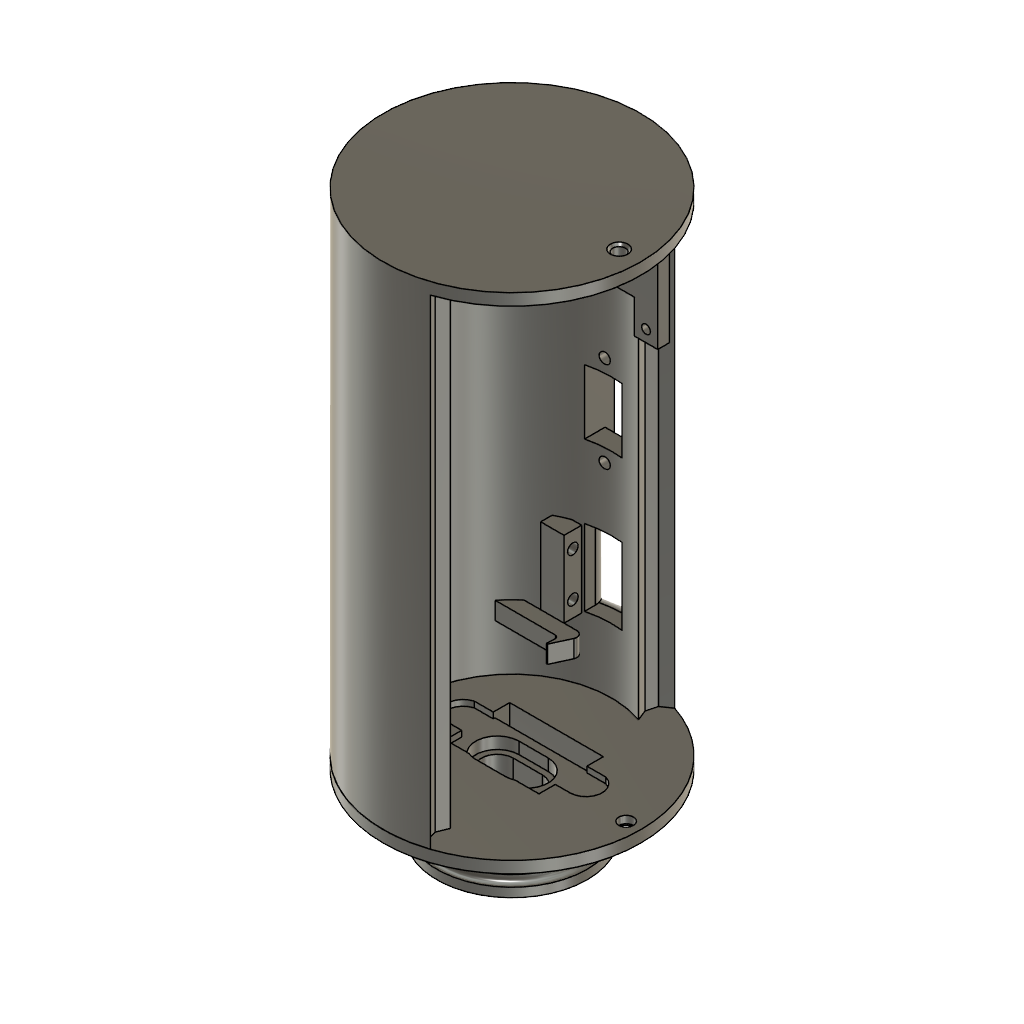
CapV3 (Autodesk Fusion 360 design; units mm, degrees)
part number: 2026-07-30-11-10-30-774
Autodesk Fusion 360 part; units mm, degrees
sketch "Sketch1" plane through (0, 0, 0) normal (0, 1, 0) x (1, 0, 0)
  line L0 (0, -15) -> (0, 25) construction
  line L1 (-12.85, 0) -> (-13.5, 0)
  circle A0 centre (-12.5, 7.5) radius 1
  line L2 (-12.85, 10) -> (-10.85, 10)
  line L3 (-10.85, 10) -> (0, 5)
  line L4 (0, 5) -> (0, 0)
  line L5 (-12.85, 10) -> (-12.85, 0)
  circle A1 centre (-12.5, 4) radius 1
  line L6 (-12.5, 7.5) -> (-11.5, 7.5) construction
  line L7 (-12.85, 0) -> (-22, 0)
  line L8 (-22, 0) -> (-22, -2)
  line L9 (-22, -2) -> (0, -2)
  line L10 (0, -2) -> (0, 0)
  dimension "d1" = 2
  dimension "d2" = 1
  dimension "d3" = 10
  dimension "d4" = 0.35
  dimension "d5" = 2
  dimension "d7" = 5
  dimension "d8" = 2.5
  dimension "d9" = 2
  dimension "d10" = 3.5
  dimension "d12" = 22
  dimension "d13" = 2
  dimension "d40" = 13.5
  dimension "d41" = 2
  dimension "d42" = 0.35
  constraint vertical L0
  constraint coincident L4.end L10.end
  constraint perpendicular L0 L1
  constraint horizontal L2
  constraint coincident L1 L4.end
  constraint perpendicular L1 L4
  constraint perpendicular L2 L5
  constraint collinear L0 L4
  constraint coincident A0.centre L6.start
  constraint coincident A0 L6.end
  constraint horizontal L6
  constraint horizontal L7
  constraint vertical L8
  constraint horizontal L9
  constraint vertical L10
  measures "d1" diameter of A0
  measures "d2" horizontal distance of L1.end A0.centre
  measures "d3" distance of L2.start L1.start
  measures "d4" distance of A0.centre L5
  measures "d5" distance of L2.start L2.end
  measures "d7" distance of L3.end L4.end
  measures "d8" vertical distance of A0.centre L2.start
  measures "d9" diameter of A1
  measures "d10" vertical distance of A0.centre A1.centre
  measures "d12" distance of L4.end L7.end
  measures "d13" distance of L4.end L9.end
  measures "d17" radius of L8.end
  measures "d40" distance of L1.end L10
  measures "d41" distance of L7.end L8.end
  measures "d42" distance of L5 A1.centre
revolve "Revolve1" add sketch "Sketch1" angle 360 about axis through (0, 0, 15) along (0, 0, -1) contours L1 A0 L2 L3 L4 L5 A1 L7 L8 L9 L10 makes body 1
sketch "Sketch2" plane through (0, 0, 2) normal (0, 0, 1) x (-1, 0, 0)
  line L0 (2.5, -3.5) -> (-2.5, -3.5)
  line L1 (-2.5, 3.5) -> (2.5, 3.5)
  arc A0 (2.5, -3.5) -> (6, 0) centre (2.5, 0) ccw
  arc A1 (6, 0) -> (2.5, 3.5) centre (2.5, 0) ccw
  arc A2 (-2.5, 3.5) -> (-6, 0) centre (-2.5, 0) ccw
  arc A3 (-6, 0) -> (-2.5, -3.5) centre (-2.5, 0) ccw
  line L2 (-2.5, 0) -> (2.5, 0) construction
  line L3 (0, -3.5) -> (0, 3.5) construction
  line L4 (-22, 0) -> (22, 0) construction
  line L5 (0, -22) -> (0, 22) construction
  arc A4 (-5.2, 0) -> (-2.5, -2.7) centre (-2.5, 0) ccw
  line L6 (2.5, -2.7) -> (-2.5, -2.7)
  arc A5 (2.5, -2.7) -> (5.2, 0) centre (2.5, 0) ccw
  arc A6 (5.2, 0) -> (2.5, 2.7) centre (2.5, 0) ccw
  line L7 (-2.5, 2.7) -> (2.5, 2.7)
  arc A7 (-2.5, 2.7) -> (-5.2, 0) centre (-2.5, 0) ccw
  arc A8 (-6.2, 0) -> (-2.5, -3.7) centre (-2.5, 0) ccw
  line L8 (2.5, -3.7) -> (-2.5, -3.7)
  arc A9 (2.5, -3.7) -> (6.2, 0) centre (2.5, 0) ccw
  arc A10 (6.2, 0) -> (2.5, 3.7) centre (2.5, 0) ccw
  line L9 (-2.5, 3.7) -> (2.5, 3.7)
  arc A11 (-2.5, 3.7) -> (-6.2, 0) centre (-2.5, 0) ccw
  circle A12 centre (0, 0) radius 22
  circle A13 centre (0, 0) radius 19.5 construction
  circle A14 centre (0, -19.5) radius 1 construction
  circle A15 centre (19.5, 0) radius 1 construction
  circle A16 centre (0, 19.5) radius 1 construction
  circle A17 centre (-19.5, 0) radius 1 construction
  point P0 (6, -3.5)
  point P1 (-6, -3.5)
  point P2 (6, 3.5)
  dimension "d15" = 12
  dimension "d16" = 7
  dimension "d17" = 3.5
  dimension "d18" = -0.8
  dimension "d37" = 0.2
  dimension "d43" = -2.5
  dimension "d51" = 2
  dimension "d53" = 360
  constraint horizontal L0
  constraint horizontal L1
  constraint coincident P0 L0
  constraint tangent L0 A0
  constraint coincident P2 L1
  constraint tangent L1 A1
  constraint equal A0 A1
  constraint coincident A0.end A1.start
  constraint tangent L1 A2
  constraint equal A0 A2
  constraint coincident P1 L0
  constraint tangent L0 A3
  constraint equal A0 A3
  constraint coincident A2.end A3.start
  constraint coincident A2.centre A3.centre
  constraint coincident A0.centre A1.centre
  constraint midpoint L0 L3.start
  constraint midpoint L1 L3.end
  constraint horizontal L4
  constraint vertical L5
  constraint collinear L2 L4
  constraint collinear L3 L5
  constraint coincident L5.start A12
  constraint coincident L5.end A12
  constraint coincident L4.start A12
  constraint coincident L4.end A12
  constraint coincident A13 A14.centre
  constraint coincident L5 A14.centre
  measures "d15" distance of P0 P1
  measures "d16" distance of P0 P2
  measures "d17" radius of A0
  measures "d51" diameter of A14
extrude "Extrude1" cut sketch "Sketch2" against normal blind 12 contours A4 L6 A5 A6 L7 A7 bodies 1
extrude "Extrude2" cut sketch "Sketch2" against normal blind 3 contours L0 L1 A0 A1 A2 A3 | A8 L8 A9 A10 L9 A11 bodies 1
sketch "Sketch3" plane through (0, 0, 2) normal (0, 0, 1) x (-1, 0, 0)
  line L0 (8, -7.6) -> (-8, -7.6)
  line L1 (-8, 3.4) -> (8, 3.4)
  line L2 (0, -7.6) -> (0, 3.4) construction
  line L3 (-8, 0) -> (8, 0) construction
  line L4 (0, -22) -> (0, 22) construction
  line L5 (-22, 0) -> (22, 0) construction
  circle A0 centre (-10.5, -2.15) radius 1.25
  line L6 (-8, 0.6) -> (-10.4994, 0.6005)
  line L7 (-11.2365, -4.8) -> (-8, -4.8)
  arc A1 (-10.4994, 0.6005) -> (-11.2365, -4.8) centre (-10.5, -2.15) ccw
  line L8 (-8, -7.6) -> (-8, -4.8)
  line L9 (-8, 0.6) -> (-8, 3.4)
  line L10 (11.2365, -4.8) -> (8, -4.8)
  arc A2 (11.2365, -4.8) -> (10.4994, 0.6005) centre (10.5, -2.15) ccw
  circle A3 centre (10.5, -2.15) radius 1.25
  line L11 (8, 0.6) -> (10.4994, 0.6005)
  line L12 (8, 3.4) -> (8, 0.6)
  line L13 (8, -4.8) -> (8, -7.6)
  line L14 (2.5, -3.5) -> (-2.5, -3.5) construction
  line L15 (-8, -7.1) -> (-8, -5.1) construction
  line L16 (-8, -5.1) -> (8, -5.1)
  line L17 (8, -5.1) -> (8, -7.1) construction
  line L18 (-10.5, -2.15) -> (10.5, -2.15) construction
  dimension "d23" = 16
  dimension "d24" = 11
  dimension "d25" = 2.5
  dimension "d26" = 2.5
  dimension "d29" = 2.8
  dimension "d30" = 4.1
  dimension "d38" = 2.5
  dimension "d39" = 2.8
  constraint horizontal L0
  constraint vertical L8
  constraint horizontal L1
  constraint vertical L12
  constraint midpoint L0 L2.start
  constraint midpoint L1 L2.end
  constraint collinear L2 L4
  constraint collinear L3 L5
  constraint coincident L6.end A1
  constraint tangent L6 A1
  constraint perpendicular L7 L8
  constraint concentric A0 A1
  constraint coincident L6 A1.start
  constraint collinear L8 L9
  constraint symmetric L4 A0 A3
  constraint symmetric L4 L6.start L11.start
  constraint symmetric L4 L6.end A2.end
  constraint symmetric L4 L7.start L10.start
  constraint symmetric L4 L7.end L10.end
  constraint symmetric L4 A1 A2
  constraint collinear L12 L13
  constraint vertical L15
  constraint horizontal L16
  constraint vertical L17
  constraint coincident A0.centre A1.centre
  constraint coincident A2.centre A3.centre
  measures "d23" distance of L0.start L0.end
  measures "d24" distance of L0.start L1.end
  measures "d25" diameter of A0
  measures "d26" distance of A0.centre L8
  measures "d29" distance of L1.start L6.start
  measures "d30" distance of L2.start L14
  measures "d38" distance of L0 L16
  measures "d39" distance of L0.start L10
extrude "Extrude3" cut sketch "Sketch3" against normal blind 1 contours L0 L8 L13 L16 | L1 L6 L7 A1 L8 L9 L10 A2 L11 L12 L13 L16 | A0 | A3 bodies 1
extrude "Extrude4" cut sketch "Sketch3" against normal blind 4 contours L0 L8 L13 L16 bodies 1
sketch "Sketch5" plane through (0, 0, 0) normal (0, 0, -1) x (1, 0, 0)
  circle A0 centre (-19.5, 0) radius 1
  circle A1 centre (19.5, 0) radius 1
  circle A2 centre (0, 19.5) radius 1
  circle A3 centre (0, -19.5) radius 1
hole "Hole1" at (19.5, 0, 0) at (0, 19.5, 0) at (0, -19.5, 0) at (-19.5, 0, 0) direction (0, 0, 1) diameter 2.5 depth 2 tip angle 118 countersink diameter 4 countersink angle 90 bodies 1
sketch "Sketch6" plane through (0, 0, 2) normal (0, 0, 1) x (-1, 0, 0)
  circle A0 centre (0, 0) radius 22
  circle A1 centre (0, 0) radius 19.5
  circle A2 centre (19.5, 0) radius 1
  circle A3 centre (-19.5, 0) radius 1
  circle A4 centre (0, -19.5) radius 1
  circle A5 centre (0, 19.5) radius 1
  circle A6 centre (0, 0) radius 17
  line L0 (-6.9351, -20.8783) -> (-5.2897, -19.7414)
  line L1 (-5.2897, -19.7414) -> (-4.8043, -17.9297)
  line L2 (-4.8043, -17.9297) -> (-5.5427, -16.071)
  line L3 (-5.694, -21.2504) -> (0, 0) construction
  line L4 (0, 0) -> (0, -22) construction
  line L5 (-5.047, -18.8356) -> (-3.6152, -19.2192) construction
  line L6 (-19.5, 0) -> (19.5, 0) construction
  line L7 (-4.8043, 17.9297) -> (-5.5427, 16.071)
  line L8 (-6.9351, 20.8783) -> (-5.2897, 19.7414)
  line L9 (-5.2897, 19.7414) -> (-4.8043, 17.9297)
  dimension "d54" = -2.5
  dimension "d59" = 2
  dimension "d60" = 2
  dimension "d62" = 15
  constraint coincident A0 L0.start
  constraint coincident A6 L2.end
  constraint coincident A0 L3.start
  constraint coincident A0.centre A1.centre
  constraint coincident A0 L4.end
  constraint vertical L4
  constraint collinear L1 L3
  constraint midpoint L1 L5.start
  constraint perpendicular L3 L5
  constraint tangent A1 L5
  constraint coincident A3.centre L6.start
  constraint coincident A2.centre L6.end
  constraint symmetric L0.start L6 L8.start
  constraint symmetric L0.end L6 L8.end
  constraint symmetric L1.end L6 L7.start
  constraint symmetric L2.end L6 L7.end
  measures "d59" distance of L0.start L0.end
  measures "d60" distance of L1.end L2.end
  measures "d62" angle of L3 L4
extrude "Extrude6" add sketch "Sketch6" along normal blind 82 separate body contours A0 A1 A3 L0 L1 L8 L9 | A1 A3 A6 L1 L2 L7 L9 | A1 A3 | A1 A3 makes body 2
ref_plane "WorkPlane2" through (0, 0, 10) normal (0, 0, 1) x (-1, 0, 0)
sketch "Sketch7" plane through (0, 0, 10) normal (0, 0, 1) x (1, 0, 0)
  line L0 (-14.6202, 10.5) -> (5.3798, 10.5) construction
  line L1 (5.3798, 10.5) -> (5.3798, -10.5) construction
  line L2 (5.3798, -10.5) -> (-14.6202, -10.5) construction
  line L3 (-14.6202, -10.5) -> (-14.6202, 10.5) construction
  line L4 (2.1268, 0) -> (-20.3732, 0) construction
  line L5 (5.3798, 0) -> (-14.6202, 0)
  line L6 (-14.6202, -10.5) -> (-3.1202, -10.5)
  line L7 (-2.6202, -10) -> (-2.6202, -8.5)
  line L8 (-2.6202, -8.5) -> (-2.4202, -8.5)
  line L9 (-2.4202, -8.5) -> (-1.0439, -11.5935)
  line L10 (-2.4202, -8.5) -> (-0.2246, -8.5) construction
  line L11 (-12.4499, -13) -> (-1.9576, -13)
  line L12 (5.3798, 0) -> (-14.6202, 0)
  line L13 (-12.4499, 13) -> (-1.9086, 13)
  line L14 (-2.6202, 8.5) -> (-2.4202, 8.5)
  line L15 (-14.6202, 10.5) -> (-3.0644, 10.5)
  line L16 (-2.5648, 9.9813) -> (-2.6202, 8.5)
  line L17 (-2.4202, 8.5) -> (-1.0004, 11.5815)
  arc A0 (-3.1202, -10.5) -> (-2.6202, -10) centre (-3.1202, -10) ccw
  arc A1 (-2.5648, 9.9813) -> (-3.0644, 10.5) centre (-3.0644, 10) ccw
  arc A2 (-1.0004, 11.5815) -> (-1.9086, 13) centre (-1.9086, 12) ccw
  arc A3 (-1.9576, -13) -> (-1.0439, -11.5935) centre (-1.9576, -12) ccw
  circle A4 centre (0, 0) radius 22
  circle A5 centre (0, 0) radius 19.5
  circle A6 centre (0, 0) radius 18
  line L18 (2.5, 0) -> (-2.5, 0)
  line L19 (22, 0) -> (-22, 0) construction
  point P0 (-2.6202, -10.5)
  point P1 (-0.6258, -13)
  dimension "d68" = 20
  dimension "d69" = 21
  dimension "d70" = 12
  dimension "d71" = 2
  dimension "d72" = 0.2
  dimension "d75" = 2.5
  dimension "d94" = 0.5
  dimension "d95" = 0.5
  dimension "d96" = 1
  dimension "d99" = -1.5
  constraint horizontal L0
  constraint vertical L1
  constraint horizontal L2
  constraint vertical L3
  constraint midpoint L1 L5.start
  constraint midpoint L3 L5.end
  constraint collinear L4 L5
  constraint perpendicular L3 L6
  constraint perpendicular L2 L7
  constraint perpendicular L7 L8
  constraint horizontal L10
  constraint horizontal L11
  constraint symmetric L2.end L5 L0.start
  constraint symmetric L12.start L5 L5.start
  constraint symmetric L12.end L5 L5.end
  constraint symmetric L5 L7.end L14.start
  constraint symmetric L5 L8.end L14.end
  constraint symmetric L5 L11.start L13.start
  constraint coincident P0 L6
  constraint coincident P0 L7
  constraint tangent L6 A0
  constraint tangent L7 A0
  constraint tangent L15 A1
  constraint tangent L16 A1
  constraint tangent L17 A2
  constraint tangent L13 A2
  constraint coincident P1 L11
  constraint tangent L11 A3
  constraint tangent L9 A3
  constraint equal A2 A3
  constraint coincident L0.start A6
  constraint collinear L12 L18
  constraint collinear L0 L15
  constraint parallel L0 L13
  constraint coincident L13.start A6
  constraint coincident A4.centre A5.centre
  measures "d68" distance of L0.start L0.end
  measures "d69" distance of L0.start L2.end
  measures "d70" distance of L2.end P0
  measures "d71" distance of P0 L7.end
  measures "d72" distance of L7.end L8.end
  measures "d75" distance of L6 L11
  measures "d94" radius of A0
  measures "d95" radius of A1
  measures "d96" radius of A2
extrude "Extrude8" add sketch "Sketch6" along normal blind 82 separate body contours A0 A1 A2 A4 A5 L0 L1 L8 L9 | A1 A2 A4 A5 A6 L1 L2 L7 L9 | A1 A5 | A1 A5 | A1 A4 | A1 A4 | A1 A2 | A1 A2 makes body 3
extrude "Extrude9" add sketch "Sketch7" along normal blind 3 contours L6 L7 L8 L9 L11 A0 A3 A6 | L13 L14 L15 L16 L17 A1 A2 A6 bodies 3
ref_plane "WorkPlane3" through (0, 0, 50) normal (0, 0, 1) x (1, 0, 0)
pattern_linear "R-Pattern1" count 2 spacing 69 along (0, 0, 1) of "Extrude9"
ref_plane "WorkPlane4" through (-10.1508, 0, 80) normal (0, 0, 1) x (-1, 0, 0)
hole "Hole2" at (0, 19.5, 2) at (0, -19.5, 2) at (-19.5, 0, 2) at (19.5, 0, 2) direction (0, 0, 1) diameter 1.8 depth 10 tip angle 118 bodies 2 3
sketch "Sketch11" plane through (0, 0, 82) normal (0, 0, 1) x (-1, 0, 0)
  line L0 (13.3697, -10.5) -> (3.0644, -10.5)
  arc A0 (2.5648, -9.9813) -> (3.0644, -10.5) centre (3.0644, -10) ccw
  line L1 (2.5648, -9.9813) -> (2.6202, -8.5)
  line L2 (2.6202, -8.5) -> (2.4202, -8.5)
  line L3 (2.4202, -8.5) -> (1.0004, -11.5815)
  arc A1 (1.0004, -11.5815) -> (1.9086, -13) centre (1.9086, -12) ccw
  line L4 (1.9086, -13) -> (10.9545, -13)
  arc A2 (10.9545, -13) -> (13.3697, -10.5) centre (0, 0) ccw
  arc A3 (-5.5427, -16.071) -> (-5.5427, 16.071) centre (0, 0) ccw
  circle A4 centre (0, 0) radius 17
  line L5 (-5.5427, -16.071) -> (-4.8043, -17.9297)
  line L6 (8.75, -14.4) -> (-8.75, -14.4) construction
  line L7 (-8.75, -14.4) -> (-8.75, -13.2) construction
  line L8 (-8.75, -13.2) -> (8.75, -13.2) construction
  line L9 (8.75, -13.2) -> (8.75, -14.4) construction
  line L10 (0, -13.2) -> (0, -14.4) construction
  line L11 (0, 0) -> (0, -22) construction
  line L12 (9.0355, -14.4) -> (-9.0355, -14.4)
  line L13 (6, -19.9) -> (-6, -19.9)
  line L14 (-6, -19.9) -> (-6, -11.9)
  line L15 (-6, -11.9) -> (6, -11.9)
  line L16 (6, -11.9) -> (6, -19.9)
  line L17 (0, -19.9) -> (0, -11.9) construction
  line L18 (-6, -15.9) -> (6, -15.9) construction
  circle A5 centre (0, 0) radius 22
  line L19 (9.75, 10.5) -> (-9.75, 10.5)
  line L20 (-9.75, 10.5) -> (-9.75, 16.25)
  line L21 (-9.75, 16.25) -> (9.75, 16.25)
  line L22 (9.75, 16.25) -> (9.75, 10.5)
  line L23 (-5.25, 16.25) -> (-5.25, 10.5)
  line L24 (5.25, 16.25) -> (5.25, 10.5)
  line L25 (9.75, 13.375) -> (5.25, 13.375) construction
  line L26 (-5.25, 13.375) -> (-9.75, 13.375) construction
  line L27 (0, 16.25) -> (0, 10.5) construction
  line L28 (3.1202, 10.5) -> (13.3697, 10.5)
  line L29 (-7.4621, 16.25) -> (-7.4621, 10.5)
  line L30 (7.5, 10.5) -> (7.5, 16.25)
  dimension "d109" = 17.5
  dimension "d110" = 1.2
  dimension "d112" = 0.2
  dimension "d115" = 12
  dimension "d116" = 8
  dimension "d117" = 1.5
  dimension "d118" = 19.5
  dimension "d119" = 5.75
  dimension "d120" = 10.5
  constraint horizontal L6
  constraint vertical L7
  constraint horizontal L8
  constraint vertical L9
  constraint midpoint L8 L10.start
  constraint midpoint L6 L10.end
  constraint collinear L10 L11
  constraint coincident A3 L12.start
  constraint coincident A4 L12.start
  constraint coincident A4 L12.end
  constraint parallel L6 L12
  constraint collinear L6 L12
  constraint horizontal L13
  constraint vertical L14
  constraint horizontal L15
  constraint vertical L16
  constraint midpoint L13 L17.start
  constraint midpoint L15 L17.end
  constraint midpoint L14 L18.start
  constraint midpoint L16 L18.end
  constraint collinear L11 L17
  constraint horizontal L19
  constraint vertical L20
  constraint horizontal L21
  constraint vertical L22
  constraint coincident L21 L23.start
  constraint coincident L19 L23.end
  constraint perpendicular L19 L23
  constraint coincident L21 L24.start
  constraint coincident L19 L24.end
  constraint perpendicular L19 L24
  constraint midpoint L22 L25.start
  constraint midpoint L24 L25.end
  constraint midpoint L23 L26.start
  constraint midpoint L20 L26.end
  constraint equal L25 L26
  constraint midpoint L21 L27.start
  constraint midpoint L19 L27.end
  constraint collinear L11 L27
  constraint collinear L19 L28
  constraint coincident L21 L29.start
  constraint coincident L19 L29.end
  constraint perpendicular L19 L29
  constraint coincident L28 L30.start
  constraint coincident L21 L30.end
  constraint perpendicular L21 L30
  measures "d109" distance of L6.start L6.end
  measures "d110" distance of L6.start L8.end
  measures "d112" distance of L4 L8
  measures "d115" distance of L13.start L13.end
  measures "d116" distance of L13.start L15.end
  measures "d117" distance of L12 L18
  measures "d118" distance of L19.start L19.end
  measures "d119" distance of L19.start L21.end
  measures "d120" distance of L23 L24
extrude "Extrude11" add sketch "Sketch11" along normal blind 2 from surface at 2 contours L0 A0 L1 L2 L3 A1 L4 A2 A3 A4 L15 L16 | L0 A0 L1 L2 L3 A1 A3 A4 L12 L14 L15 L19 L20 L28 | L4 A3 A4 L12 L16 | A1 L4 L12 L14 L15 L16 | A1 L4 L15 L16 | A3 A4 L12 L16 | A3 A4 L22 L28 | A3 A4 L12 L14 L16 | A3 A4 L13 L14 L16 | A3 A4 L19 L22 L28 L30 | A3 A4 L21 L22 L30 | A4 L12 L14 | A3 A4 L19 L24 L28 L30 | A3 A4 L21 L24 L30 | A3 A4 L19 L21 L23 L24 L28 | A3 A4 L21 L24 | A4 L20 L21 L29 | A4 L19 L20 L29 | A3 A4 L21 | A3 A4 L21 L23 L29 | A3 A4 L19 L23 L29 | A3 A4 L21 L23 | A5 bodies 3
sketch "Sketch12" plane through (0, 0, 0) normal (1, 0, 0) x (0, 1, 0)
  line L0 (13, 79) -> (11.5815, 79)
  line L1 (13, 79) -> (13, 82)
  line L2 (13, 82) -> (11.5815, 82)
  line L3 (11.5815, 82) -> (11.5815, 79)
  line L4 (10.5, 79) -> (10.5, 82)
  line L5 (10.5, 82) -> (13, 82)
  line L6 (13, 82) -> (13, 79)
  line L7 (13, 79) -> (10.5, 79)
  line L8 (-13, 79) -> (-13, 82)
  line L9 (-13, 82) -> (-10.5, 82)
  line L10 (-10.5, 82) -> (-10.5, 79)
  line L11 (-10.5, 79) -> (-13, 79)
  line L12 (10.5, 10) -> (10.5, 13)
  line L13 (10.5, 13) -> (13, 13)
  line L14 (13, 13) -> (13, 10)
  line L15 (13, 10) -> (10.5, 10)
  line L16 (-13, 10) -> (-13, 13)
  line L17 (-13, 13) -> (-10.5, 13)
  line L18 (-10.5, 13) -> (-10.5, 10)
  line L19 (-10.5, 10) -> (-13, 10)
  line L20 (17, 2) -> (-17, 2)
  line L21 (16.071, 2) -> (16.071, 84)
  line L22 (-17, 84) -> (17, 84)
  line L23 (-16.071, 84) -> (-16.071, 2)
  point P0 (13, 79)
sketch "Sketch13" plane through (0, 0, 0) normal (0, 1, 0) x (1, 0, 0)
  line L0 (-1.9086, -79) -> (-0.9086, -79)
  line L1 (-1.9086, -79) -> (-1.9086, -82)
  line L2 (-1.9086, -82) -> (-0.9086, -82)
  line L3 (-1.0004, -82) -> (-1.0004, -79)
  line L4 (-10.6041, -79) -> (11.8959, -79) construction
  line L5 (11.8959, -79) -> (11.8959, -61.5)
  line L6 (11.8959, -61.5) -> (-10.6041, -61.5) construction
  line L7 (-10.6041, -61.5) -> (-10.6041, -79) construction
  circle A0 centre (9.8959, -77) radius 0.75
  circle A1 centre (9.8959, -63.5) radius 0.75
  line L8 (11.8959, -70.25) -> (-4.1041, -70.25) construction
  line L9 (-4.1041, -73.25) -> (11.8959, -73.25)
  line L10 (11.8959, -73.25) -> (11.8959, -67.25) construction
  line L11 (11.8959, -67.25) -> (-4.1041, -67.25)
  line L12 (-4.1041, -67.25) -> (-4.1041, -73.25)
  line L13 (11.8959, -79) -> (7.8959, -79)
  line L14 (11.8959, -61.5) -> (7.8959, -61.5)
  line L15 (7.8959, -79) -> (7.8959, -61.5)
  line L16 (11.8959, -61.5) -> (11.8959, -79) construction
  line L17 (6.9351, -84) -> (6.9351, -2)
  line L18 (-22, -2) -> (6.9351, -2)
  line L19 (6.9351, -2) -> (6.9351, -84)
  line L20 (5.5427, -2) -> (5.5427, -84)
  line L21 (5.5427, -2) -> (4.8043, -2)
  line L22 (4.8043, -2) -> (4.8043, -84)
  line L23 (4.8043, -84) -> (5.5427, -84)
  line L24 (5.5427, -84) -> (5.5427, -2)
  line L25 (5.5427, -73.25) -> (5.5427, -67.25)
  line L26 (-4.1041, -54) -> (1.8959, -54)
  line L27 (1.8959, -54) -> (1.8959, -34)
  line L28 (1.8959, -34) -> (-4.1041, -34)
  line L29 (-4.1041, -34) -> (-4.1041, -54)
  line L30 (1.8959, -44) -> (-4.1041, -44) construction
  line L31 (-4.1041, -49.5) -> (1.8959, -49.5)
  line L32 (1.8959, -38.5) -> (-4.1041, -38.5)
  line L33 (6.9351, -43) -> (4.8043, -43) construction
  line L34 (-1.1041, -86) -> (-1.1041, -2) construction
  line L35 (-4.1041, -26) -> (1.8959, -26)
  line L36 (1.8959, -26) -> (1.8959, -13)
  line L37 (1.8959, -13) -> (-4.1041, -13)
  line L38 (-4.1041, -13) -> (-4.1041, -26)
  line L39 (1.8959, -19.5) -> (-4.1041, -19.5) construction
  line L40 (-1.9086, -10) -> (-0.9086, -10) construction
  line L41 (-1.9086, -10) -> (-1.9086, -13) construction
  line L42 (-1.9086, -13) -> (-0.9086, -13) construction
  line L43 (-1.0004, -13) -> (-1.0004, -10) construction
  line L44 (-1.1041, -13) -> (-1.1041, -26) construction
  line L45 (-4.1041, -13) -> (-8.1041, -13)
  line L46 (-8.1041, -13) -> (-8.1041, -26)
  line L47 (-8.1041, -26) -> (-4.1041, -26)
  line L48 (12.8959, -60.5) -> (6.8959, -60.5)
  line L49 (6.8959, -80) -> (6.8959, -60.5)
  line L50 (12.8959, -80) -> (6.8959, -80)
  line L51 (12.8959, -80) -> (12.8959, -60.5)
  line L52 (-22, -86) -> (22, -86)
  line L53 (6.9351, -84) -> (22, -84)
  dimension "d134" = 22.5
  dimension "d135" = 17.5
  dimension "d136" = 1.5
  dimension "d137" = 2
  dimension "d138" = 2
  dimension "d139" = 2
  dimension "d140" = 2
  dimension "d141" = 16
  dimension "d142" = 6
  dimension "d143" = 16
  dimension "d144" = 4
  dimension "d145" = 4
  dimension "d152" = 1.5
  dimension "d153" = 6
  dimension "d154" = 20
  dimension "d155" = 5.5
  dimension "d156" = 5.5
  dimension "d157" = 6
  dimension "d158" = 13
  dimension "d180" = 3
  dimension "d183" = -1
  constraint horizontal L4
  constraint vertical L5
  constraint horizontal L6
  constraint vertical L7
  constraint collinear L0 L4
  constraint midpoint L5 L8.start
  constraint perpendicular L5 L8
  constraint horizontal L9
  constraint vertical L10
  constraint horizontal L11
  constraint vertical L12
  constraint midpoint L8.end L12
  constraint perpendicular L5 L13
  constraint perpendicular L5 L14
  constraint coincident L9 L25.start
  constraint coincident L24 L25.start
  constraint coincident L11 L25.end
  constraint coincident L24 L25.end
  constraint horizontal L26
  constraint vertical L27
  constraint horizontal L28
  constraint vertical L29
  constraint midpoint L27 L30.start
  constraint midpoint L29 L30.end
  constraint coincident L29 L31.start
  constraint coincident L27 L31.end
  constraint perpendicular L27 L31
  constraint coincident L27 L32.start
  constraint coincident L29 L32.end
  constraint perpendicular L29 L32
  constraint midpoint L17 L33.start
  constraint midpoint L22 L33.end
  constraint coincident L18 L34.end
  constraint perpendicular L18 L34
  constraint midpoint L30 L34
  constraint horizontal L35
  constraint vertical L36
  constraint horizontal L37
  constraint vertical L38
  constraint midpoint L36 L39.start
  constraint midpoint L38 L39.end
  constraint collinear L37 L42
  constraint midpoint L37 L44.start
  constraint midpoint L35 L44.end
  constraint collinear L34 L44
  constraint perpendicular L38 L45
  constraint perpendicular L37 L46
  measures "d134" distance of L4.start L4.end
  measures "d135" distance of L4.start L6.end
  measures "d136" diameter of A0
  measures "d137" distance of L5 A0.centre
  measures "d138" distance of L4 A0.centre
  measures "d139" distance of L6 A1.centre
  measures "d140" distance of L5 A1.centre
  measures "d141" distance of L8.start L8.end
  measures "d142" distance of L9.start L11.end
  measures "d143" distance of L10.end L11.end
  measures "d144" distance of L4.end L13.end
  measures "d145" distance of L5.end L14.end
  measures "d152" diameter of A1
  measures "d153" distance of L26.start L26.end
  measures "d154" distance of L26.start L28.end
  measures "d155" distance of L30 L32
  measures "d156" distance of L30 L31
  measures "d157" distance of L35.start L35.end
  measures "d158" distance of L35.start L37.end
  measures "d180" distance of L12 L34
extrude "Extrude13" add sketch "Sketch13" along normal blind 2 from surface at 13 separate body contours L5 L9 L13 L15 | L5 L9 L11 L15 | L5 L11 L14 L15 | L9 L11 L15 L17 L19 | L9 L11 L17 L19 L49 | L9 L11 L20 L24 L25 L49 | L9 L11 L20 L22 L24 L25 | L9 L11 L12 L22 makes body 4
extrude "Extrude14" add sketch "Sketch13" along normal blind 3 from surface at 15 contours L9 L11 L12 L22 bodies 3 4
extrude "Extrude15" cut sketch "Sketch13" along normal blind 4 from surface at 20 contours L26 L27 L29 L31 | L27 L29 L31 L32 | L27 L28 L29 L32 bodies 3
extrude "Extrude16" cut sketch "Sketch13" along normal blind 27.5 contours L27 L29 L31 L32 bodies 3
extrude "Extrude17" cut sketch "Sketch13" along normal blind 33 contours L35 L36 L37 L38 bodies 3
extrude "Extrude18" add sketch "Sketch13" against normal blind 3 from surface at 16 contours L38 L45 L46 L47 bodies 3
sketch "Sketch14" plane through (-4.1041, 0, 0) normal (1, 0, 0) x (0, 1, 0)
  circle A0 centre (14.5131, 15.75) radius 0.9
  line L0 (16, 13) -> (13, 13)
  line L1 (14.5, 13) -> (14.5, 26) construction
  circle A1 centre (14.5, 23.25) radius 0.9
  line L2 (16, 26) -> (13, 26)
  dimension "d169" = 1.8
  dimension "d170" = 2.75
  dimension "d171" = 1.8
  dimension "d172" = 2.75
  constraint midpoint L0 L1.start
  constraint perpendicular L0 L1
  constraint coincident L1 A1.centre
  measures "d169" diameter of A0
  measures "d170" distance of A0.centre L0
  measures "d171" diameter of A1
  measures "d172" distance of A1.centre L2
extrude "Extrude19" cut sketch "Sketch14" against normal blind 4 bodies 3
sketch "Sketch15" plane through (0, 0, 0) normal (1, 0, 0) x (0, 1, 0)
  line L0 (13, 79) -> (13, 61.5) construction
  line L1 (13, 61.5) -> (15, 61.5)
  line L2 (15, 61.5) -> (15, 79) construction
  line L3 (15, 79) -> (13, 79)
  line L4 (7, 76.25) -> (15, 76.25)
  line L5 (15, 76.25) -> (15, 64.25)
  line L6 (15, 64.25) -> (7, 64.25)
  line L7 (7, 64.25) -> (7, 76.25)
  line L8 (14, 61.5) -> (14, 79) construction
  line L9 (15, 70.25) -> (13, 70.25) construction
  line L10 (11, 76.25) -> (11, 64.25)
  line L11 (15, 70.25) -> (7, 70.25)
  dimension "d175" = 8
  dimension "d176" = 12
  dimension "d177" = 3
  constraint horizontal L4
  constraint vertical L5
  constraint horizontal L6
  constraint vertical L7
  constraint midpoint L1 L8.start
  constraint midpoint L3 L8.end
  constraint midpoint L2 L9.start
  constraint midpoint L0 L9.end
  constraint midpoint L4 L10.start
  constraint midpoint L6 L10.end
  constraint midpoint L5 L9.start
  constraint midpoint L7 L11.end
  constraint collinear L9 L11
  measures "d175" distance of L4.start L4.end
  measures "d176" distance of L4.start L6.end
  measures "d177" distance of L8 L10
extrude "Extrude20" cut sketch "Sketch15" along normal blind 21 bodies 2
extrude "Extrude21" cut sketch "Sketch13" along normal blind 15 contours L5 L9 L13 L15 | L5 L9 L11 L13 L14 L15 L17 L19 L48 L50 L51 | L5 L9 L11 L15 | L5 L11 L14 L15 | L9 L11 L15 L17 L19 | L9 L17 L19 L49 L50 | L9 L11 L17 L19 L49 | L11 L17 L19 L48 L49 | L9 L11 L20 L22 L24 L25 | A0 | A1 bodies 2
hole "Hole5" at (-1.1041, 20, 36.25) direction (0, -1, 0) diameter 1.8 depth 5 tip angle 180 bodies 3
hole "Hole6" at (-1.1041, 20, 51.75) direction (0, -1, 0) diameter 1.8 depth 5 tip angle 180 bodies 3
sketch "Sketch16" plane through (0, 0, 86) normal (0, 0, 1) x (-1, 0, 0)
  arc A0 (-6.9351, 20.8783) -> (-6.9351, -20.8783) centre (0, 0) ccw
  line L0 (-6.9351, -20.8783) -> (-5.2897, -19.7414)
  line L1 (-5.2897, -19.7414) -> (-4.8043, -17.9297)
  line L2 (-4.8043, -17.9297) -> (-5.5427, -16.071)
  arc A1 (-5.5427, 16.071) -> (-5.5427, -16.071) centre (0, 0) ccw
  line L3 (-5.5427, 16.071) -> (-4.8043, 17.9297)
  line L4 (-4.8043, 17.9297) -> (-5.2897, 19.7414)
  line L5 (-5.2897, 19.7414) -> (-6.9351, 20.8783)
  line L6 (-22, 0) -> (-17, 0) construction
  line L7 (-19.5, -0.3175) -> (-19.5, 0.3175) construction
  constraint midpoint A0 L6.start
  constraint midpoint A1 L6.end
  constraint vertical L7
  constraint midpoint L6 L7
hole "Hole7" at (18.2505, 0.0505, 86) direction (0, 0, -1) diameter 2.2 depth 2 tip angle 180 countersink diameter 3 countersink angle 90 bodies 3
hole "Hole8" at (19.42, -0.0001, 84) direction (0, 0, -1) diameter 1.8 depth 10 tip angle 180 bodies 2
fillet "Fillet1" radius 2.5 3 edges at (-1.1146, 21.9717, 13) (-4.1041, 21.6138, 19.5) (1.8959, 21.9182, 19.5) on bodies 3
hidden bodies 2
equation "d12 = ( ( 35 / 2 ) * 1 mm ) + 4.5 mm"
equation "d170 = 2 mm + ( 1.5 / 2 ) * 1 mm"
